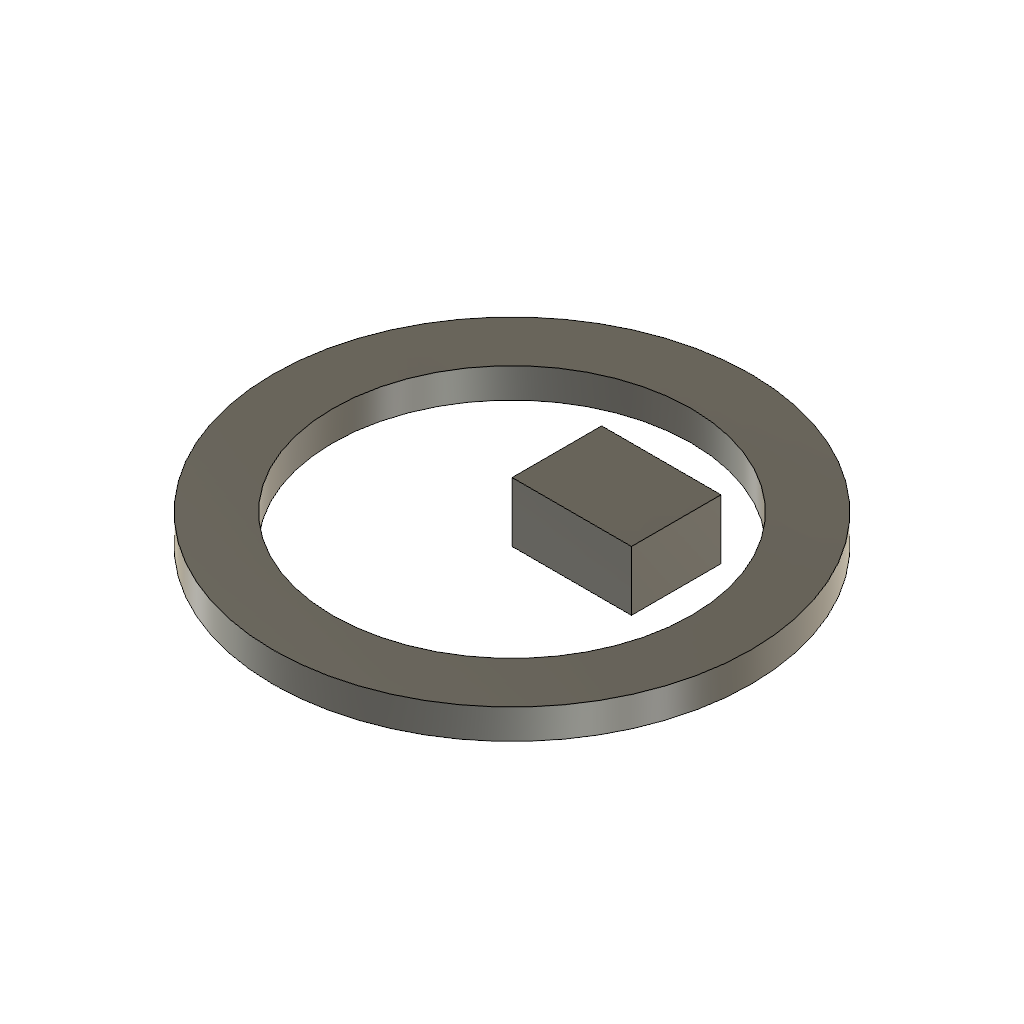
RevolveBody (Autodesk Fusion 360 design; units mm, degrees)
part number: 2026-11-12-20-32-23-152
Autodesk Fusion 360 part; units mm, degrees
sketch "Base sketch" plane through (0, 0, 0) normal (0, 0, 1) x (1, 0, 0)
  line L0 (0, 0) -> (40, 0)
  line L1 (40, 0) -> (40, 30)
  line L2 (40, 30) -> (0, 30)
  line L3 (0, 30) -> (0, 0)
extrude "Base extrude" add sketch "Base sketch" along normal blind 20 makes body 1
sketch "Ring sketch" plane through (0, 0, 0) normal (0, 1, 0) x (1, 0, 0)
  line L0 (60, 0) -> (80, 0)
  line L1 (80, 0) -> (80, -10)
  line L2 (80, -10) -> (60, -10)
  line L3 (60, -10) -> (60, 0)
revolve "Ring revolve" add sketch "Ring sketch" angle 360 about axis through (0, 0, 1.75) along (0, 0, 1) separate body makes body 2
